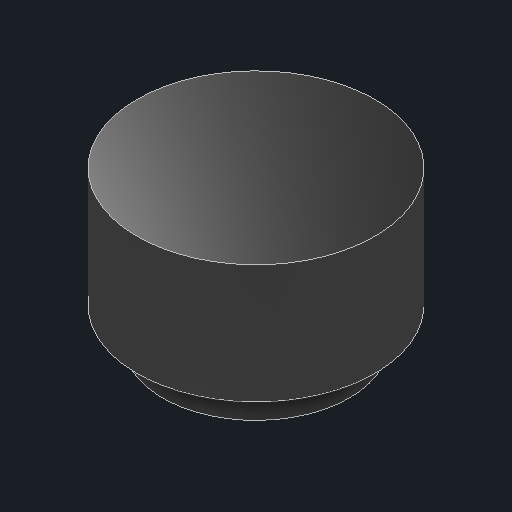
# Autodesk Inventor part: counterweight_stop
Saved by Autodesk Inventor 2027.1 (Build 311270010, 270A)
## iProperties
Created: 2026-11-04
Part Number: counterweight_stop
Material: Generic
Description: Counterweight bar safety stop
Document SubType Name: Modeling
Designer: Claude (from photos)
Density: 1 g/cm^3
Appearance: Glossy - Black
Author: alexg
Autodesk Inventor part; units mm, degrees
ref_plane "YZ Plane" through (0, 0, 0) normal (1, 0, 0) x (0, 1, 0)
ref_plane "Work Plane1" through (0, -450, 0) normal (0, 1, 0) x (-1, 0, 0)
sketch "Safety stop sketch" plane through (0, -450, 0) normal (0, 1, 0) x (-1, 0, 0)
  circle A0 centre (-187, 0) radius 14
  constraints: 1 centre point
extrude "Safety stop" add sketch "Safety stop sketch" against normal blind 14
ref_plane "Work Plane2" through (0, -464, 0) normal (0, 1, 0) x (-1, 0, 0)
sketch "Stop cap sketch" plane through (0, -464, 0) normal (0, 1, 0) x (-1, 0, 0)
  circle A0 centre (-187, 0) radius 11
  constraints: 1 centre point
extrude "Stop cap" add sketch "Stop cap sketch" against normal blind 4
body "Solid1"
